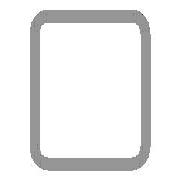
# Autodesk Inventor part: DIN EN 10219-2 - 80 x 80 x 5  - 108,9
Saved by Autodesk Inventor 2025.3 (Build 293356000, 356)
## iProperties
IsCustomPart: 1
Created: 2024-01-20
Part Number: DIN EN 10219-2 - 80 x 80 x 5  - 108,9
Material: Aluminium 6061
Description: Kaltgeformte, geschweißte Baustahl-Hohlprofile aus unlegiertem Feinkorn-Baustahl
Document SubType Name: Modeling
Standard: DIN EN 10219-2
Designer: sebas
Standard Revision: 2006-07
Standards Organization: DIN
Language: de-DE
Size Designation: 80 x 80 x 5  - 108,9
Categories: <MemberInstance><Categories><Category DisplayName="Profile" InternalName="089c4875-fa83-4c05-b084-43b9cc11f5ed" Mnemonic="GRDR"><CategoryParameter DisplayName="Masse pro Längeneinheit" InternalName="0bb95a10-148f-4027-a459-38d7b056702a" Mnemonic="shpmass"/><CategoryParameter DisplayName="Querschnittsfläche" InternalName="1ff91680-64b0-4202-b9a3-7fd3f94bba3b" Mnemonic="secarea"/><CategoryParameter DisplayName="Trägheitsradius (x)" InternalName="25778675-03e9-40c1-b6a8-4a9ed693320d" Mnemonic="gyrradx"/><CategoryParameter DisplayName="Torsion-Festigkeitsmodul" InternalName="26c1ec35-5026-4c63-ad0a-751cf684a536" Mnemonic="torrigmod"/><CategoryParameter DisplayName="Abstand zum Schwerpunkt X-X" InternalName="26c9bdb8-9c79-4b4f-a92e-8e197583c9c4" Mnemonic="grcendistX"/><CategoryParameter DisplayName="Alte Varianten-ID" InternalName="340afe4f-75d7-48d3-ab7d-943f3c3da468" Mnemonic="LegacyMemberID"/><CategoryParameter DisplayName="Basislänge" InternalName="42e34263-8f20-4d0e-ad48-bf1385b87c24" Mnemonic="shplen"/><CategoryParameter DisplayName="Trägheitsmoment (y)" InternalName="4b9f58ea-bced-460e-81ea-3d29ca5a49e3" Mnemonic="inermomy"/><CategoryParameter DisplayName="Trägheitsmoment (x)" InternalName="4cd780bc-73d7-43ac-917a-579e5cbd684d" Mnemonic="inermomx"/><CategoryParameter DisplayName="Benutzerdefinierter Basispunkt" InternalName="4f1d1b73-316d-484b-a3df-9cbabb16eb77" Mnemonic="shpBasePoint"/><CategoryParameter DisplayName="Objekthöhe" InternalName="50274e7d-5ac0-4796-92cb-c59e54983c67" Mnemonic="shpheig"/><CategoryParameter DisplayName="Widerstandsmoment (y)" InternalName="59eaa5e9-d227-48dc-b6c1-6920f96e0f95" Mnemonic="secmody"/><CategoryParameter DisplayName="Schnittbezeichnung" InternalName="5a64d034-428d-49c8-ba32-7619764de20f" Mnemonic="shpdes"/><CategoryParameter DisplayName="Widerstandsmoment (x)" InternalName="72cfad18-cf51-4ed4-aaa7-c6b224f8419f" Mnemonic="secmodx"/><CategoryParameter DisplayName="Drehrissmodul" InternalName="7c55a8dc-8844-49f9-a867-cc677b30ec9a" Mnemonic="torsecmod"/><CategoryParameter DisplayName="Objektbreite" InternalName="7c717d54-a18f-4666-b4d4-573cce22c62c" Mnemonic="shpwdth"/><CategoryParameter DisplayName="Zweite Objektdicke" InternalName="9251a8e1-85fd-4e47-af99-afdb762317d9" Mnemonic="shpthick2"/><CategoryParameter DisplayName="GG Erstellt" InternalName="9c666724-f362-4ea7-ac62-f6a007de5c69" Mnemonic="shpFGAuto"/><CategoryParameter DisplayName="Abstand zum Schwerpunkt Y-Y" InternalName="bcc4fb17-7af4-436a-8f8c-d0aa3b0248c5" Mnemonic="grcendistY"/><CategoryParameter DisplayName="Trägheitsradius (y)" InternalName="bfa18ebe-1636-4dbe-8d42-b263e0b73184" Mnemonic="gyrrady"/><CategoryParameter DisplayName="Objektdicke" InternalName="d109cf76-8eb4-42fc-9800-4409734adc67" Mnemonic="shpthick"/><CategoryParameter DisplayName="Koeffizient für Schubverschiebung" InternalName="de4c90c6-aaa8-468f-a335-6737b311b5d3" Mnemonic="shdispc"/><Category DisplayName="Vierkantrohre (quadratisch/rechteckig)" InternalName="afc8e2d8-05d6-4609-8807-f98a9b7d2ed0" Mnemonic="SQRSHP"><CategoryParameter DisplayName="Querschnittsfläche" InternalName="2f7f79dd-983c-4263-802a-5b6a1495fdc5" Mnemonic="secarea"/><CategoryParameter DisplayName="Widerstandsmoment (x)" InternalName="50d965a6-04bf-46b9-8ace-861858d348e6" Mnemonic="secmodx"/><CategoryParameter DisplayName="Widerstandsmoment (y)" InternalName="5106aeac-54a2-4159-a9af-8933dd39dba2" Mnemonic="secmody"/><CategoryParameter DisplayName="Objektdicke" InternalName="52712fc5-f4ee-4eda-b3f2-6fce82c26419" Mnemonic="shpthick"/><CategoryParameter DisplayName="Trägheitsmoment (y)" InternalName="55ec8510-8276-4c45-8f10-594e0fee7eb3" Mnemonic="inermomy"/><CategoryParameter DisplayName="Trägheitsradius (x)" InternalName="56c89926-a299-4389-a862-ac94c9691272" Mnemonic="gyrradx"/><CategoryParameter DisplayName="Radius" InternalName="5d8d062c-e28e-41c1-98da-8e5fee36da1a" Mnemonic="shprad"/><CategoryParameter DisplayName="Trägheitsmoment (x)" InternalName="8c4637b6-6b69-4878-9d5d-26a32185d655" Mnemonic="inermomx"/><CategoryParameter DisplayName="Objektbreite" InternalName="8c8a1782-5e80-4d77-858b-304b1c0ad1fd" Mnemonic="shpwdth"/><CategoryParameter DisplayName="Trägheitsradius (y)" InternalName="fa48a7f5-f030-40f9-a60b-de8a845b7104" Mnemonic="gyrrady"/></Category></Category><Category DisplayName="Datentyp" InternalName="23b78d0f-2648-40c6-8793-ca6db495c9e8" Mnemonic="DATATYPE"><CategoryParameter DisplayName="Anzeigename" InternalName="05415f3d-3907-474b-a020-eb9d644f4cf3" Mnemonic="DISPLAYNAME"/><CategoryParameter DisplayName="Norm" InternalName="0c0a119c-1e12-4c84-803f-101930972f5e" Mnemonic="STANDARD"/><CategoryParameter DisplayName="Beschreibung" InternalName="13903e3d-64b1-4950-80da-f627842ea37f" Mnemonic="DESCRIPTION"/><CategoryParameter DisplayName="Bezeichnung" InternalName="2675968c-4ce5-49e0-a4f5-552d29089031" Mnemonic="DESIGNATION"/><CategoryParameter DisplayName="Standardzeile" InternalName="2af9ec52-faaa-4026-b378-f9fa4afca842" Mnemonic="DEFAULTROW"/><CategoryParameter DisplayName="Ordnername" InternalName="3f06958e-8713-4116-9be7-ed6184ecc97b" Mnemonic="FOLDERNAME"/><CategoryParameter DisplayName="Revisionsanleitung" InternalName="45a75005-10b1-4dfc-8d6d-dfe629f0b93c" Mnemonic="REVISIONGUID"/><CategoryParameter DisplayName="Dateiname" InternalName="8b46a4cc-9585-4fed-90c3-899f57e09a73" Mnemonic="FILENAME"/><CategoryParameter DisplayName="Normungsorganisation" InternalName="8f5914e1-4693-403f-8ab5-d37768198c9d" Mnemonic="STDSORG"/><CategoryParameter DisplayName="Gruppenversion" InternalName="914462f6-6e19-4b14-ba84-155b9680b1d0" Mnemonic="FAMILYREVISION"/><CategoryParameter DisplayName="Normrevision" InternalName="91d5a463-65c2-4fde-b823-3b7fea5e8e17" Mnemonic="STANDARDREVISION"/><CategoryParameter DisplayName="Variantenrevision" InternalName="a65d44b9-392f-4f4f-857b-e4b3d54996fe" Mnemonic="MEMBERREVISION"/><CategoryParameter DisplayName="ClipFormat" InternalName="bc51e27b-3422-4e78-93ef-cec197ddf230" Mnemonic="CLIPFORMAT"/><CategoryParameter DisplayName="Hersteller" InternalName="cd6c7a72-a28a-4e50-99a9-2c7f4e13e5ad" Mnemonic="MANUFACTURER"/><CategoryParameter DisplayName="InternerName" InternalName="cf1d0246-76d9-4b4a-8305-fa0409afb5c1" Mnemonic="INTERNALNAME"/><CategoryParameter DisplayName="IstMetrisch" InternalName="e2385c5b-1ea4-4823-96a8-8de651266ec3" Mnemonic="ISMETRIC"/><Category DisplayName="Bauteil" InternalName="c0e0b642-3bcb-4cc8-9e80-f96d35c4afa4" Mnemonic="PART"><CategoryParameter DisplayName="Bauteilnummer" InternalName="016b6077-bfbe-49bd-92c9-d8d59c39c941" Mnemonic="PARTNUMBER"/><CategoryParameter DisplayName="Bestandsnummer" InternalName="4dba7c1c-e26c-444e-836c-b08b433409a8" Mnemonic="STOCKNUMBER"/><CategoryParameter DisplayName="Materialschlüssel" InternalName="5c9a8adb-dd2b-4535-b97f-0a94a95fe41f" Mnemonic="MATERIALKEY"/><CategoryParameter DisplayName="Material" InternalName="818a152a-d3c3-49ca-80ee-df7d91421b8e" Mnemonic="MATERIAL"/></Category></Category><Category DisplayName="ÄltereVersionenzuweisen" InternalName="cd87c42b-3e48-431e-b5c0-1cbeb14dfe77" Mnemonic="LEGACYMAP"><CategoryParameter DisplayName="Eindeutige DA-Varianten-ID" InternalName="0918ad47-427f-4fed-ae26-24c81c58f590" Mnemonic="DACOOKIE"/><CategoryParameter DisplayName="ID zusammenführen" InternalName="0ee8fb18-e2ed-4f39-96f6-1f4b5f50aa71" Mnemonic="MERGE11"/><CategoryParameter DisplayName="Eindeutige CC-Varianten-ID" InternalName="5193edd4-b2b0-4ab4-9d54-de900eee34e0" Mnemonic="CCCOOKIE"/><CategoryParameter DisplayName="ID aufteilen" InternalName="72b5c83c-be7f-45c4-ae51-9160ea6deb26" Mnemonic="SPLIT"/><CategoryParameter DisplayName="VarianteID" InternalName="8e5e0294-fc51-4c8f-b3d7-003dc5ed94f6" Mnemonic="MEMBERID"/><CategoryParameter DisplayName="Katalogname" InternalName="d99d1e27-aa94-4de2-af4c-c348882a6f4f" Mnemonic="CATALOGNAME"/><CategoryParameter DisplayName="Gruppennummer" InternalName="e705e1f4-09cb-413e-91f9-551b4188271e" Mnemonic="FAMILYNUMBER"/></Category></Categories><FamilyTemplate Id="gp0601"><FamilyTemplateParameters><FamilyTemplateParameter ObjectType="kUserParameterObject" ValueType="xs:double" Id="1" ObjectReferenceKey="G_H"/><FamilyTemplateParameter ObjectType="kUserParameterObject" ValueType="xs:double" Id="2" ObjectReferenceKey="B_L"/><FamilyTemplateParameter ObjectType="kUserParameterObject" ValueType="xs:double" Id="6" ObjectReferenceKey="G_W"/><FamilyTemplateParameter ObjectType="kUserParameterObject" ValueType="xs:double" Id="7" ObjectReferenceKey="G_T"/><FamilyTemplateParameter ObjectType="kUserParameterObject" ValueType="xs:double" Id="8" ObjectReferenceKey="G_IR"/><FamilyTemplateParameter ObjectType="kPropertyObject" ValueType="xs:string" Id="100" ObjectReferenceKey="{32853F0F-3444-11d1-9E93-0060B03C1CA6}" SubObjectId="52"/><FamilyTemplateParameter ObjectType="kPropertyObject" ValueType="xs:string" Id="105" ObjectReferenceKey="{32853F0F-3444-11d1-9E93-0060B03C1CA6}" SubObjectId="5"/><FamilyTemplateParameter ObjectType="kPartComponentDefinitionObject" ValueType="xs:string" Id="110" SubObjectId="Material"/><FamilyTemplateParameter ObjectType="kPropertyObject" ValueType="xs:string" Id="112" ObjectReferenceKey="{32853F0F-3444-11d1-9E93-0060B03C1CA6}" SubObjectId="55"/></FamilyTemplateParameters></FamilyTemplate><CategoryParameterMap><ParamToTemplateMap><ParamToTemplate CategoryParameter="//CategoryParameter[@InternalName='05415f3d-3907-474b-a020-eb9d644f4cf3']" ConstantValue="DIN EN 10219-2 (Square Hollow Section - Cold Formed)"/><ParamToTemplate CategoryParameter="//CategoryParameter[@InternalName='cf1d0246-76d9-4b4a-8305-fa0409afb5c1']" ConstantValue="f4eb4807-7530-48bf-9740-f5a60eee53a8"/><ParamToTemplate CategoryParameter="//CategoryParameter[@InternalName='3f06958e-8713-4116-9be7-ed6184ecc97b']" ConstantValue="DIN EN 10219-2(1)"/><ParamToTemplate CategoryParameter="//CategoryParameter[@InternalName='914462f6-6e19-4b14-ba84-155b9680b1d0']" ConstantValue="10"/><ParamToTemplate CategoryParameter="//CategoryParameter[@InternalName='bc51e27b-3422-4e78-93ef-cec197ddf230']" ConstantValue="CF_INVENTOR.STDPARTS"/><ParamToTemplate CategoryParameter="//CategoryParameter[@InternalName='e2385c5b-1ea4-4823-96a8-8de651266ec3']" ConstantValue="true"/><ParamToTemplate CategoryParameter="//CategoryParameter[@InternalName='13903e3d-64b1-4950-80da-f627842ea37f']" ConstantValue="Cold formed welded structural hollow sections of non-alloy and fine grain structural steel"/><ParamToTemplate CategoryParameter="//CategoryParameter[@InternalName='8f5914e1-4693-403f-8ab5-d37768198c9d']" ConstantValue="DIN"/><ParamToTemplate CategoryParameter="//CategoryParameter[@InternalName='0c0a119c-1e12-4c84-803f-101930972f5e']" ConstantValue="DIN EN 10219-2"/><ParamToTemplate CategoryParameter="//CategoryParameter[@InternalName='cd6c7a72-a28a-4e50-99a9-2c7f4e13e5ad']" TemplateParameter="104"/><ParamToTemplate CategoryParameter="//CategoryParameter[@InternalName='91d5a463-65c2-4fde-b823-3b7fea5e8e17']" ConstantValue="2006-07"/><ParamToTemplate CategoryParameter="//CategoryParameter[@InternalName='45a75005-10b1-4dfc-8d6d-dfe629f0b93c']" ConstantValue="fa0180ad-9900-4c48-9c99-ee51de72b725"/><ParamToTemplate CategoryParameter="//CategoryParameter[@InternalName='2af9ec52-faaa-4026-b378-f9fa4afca842']" ConstantValue="1"/><ParamToTemplate CategoryParameter="//CategoryParameter[@InternalName='9c666724-f362-4ea7-ac62-f6a007de5c69']" ConstantValue="1"/><ParamToTemplate CategoryParameter="//CategoryParameter[@InternalName='d99d1e27-aa94-4de2-af4c-c348882a6f4f']" ConstantValue="BSI"/><ParamToTemplate CategoryParameter="//CategoryParameter[@InternalName='e705e1f4-09cb-413e-91f9-551b4188271e']" ConstantValue="158"/><ParamToTemplate CategoryParameter="//CategoryParameter[@InternalName='8b46a4cc-9585-4fed-90c3-899f57e09a73']" ConstantValue="DIN EN 10219-2 - 80 x 80 x 5  - 108,9"/><ParamToTemplate CategoryParameter="//CategoryParameter[@InternalName='a65d44b9-392f-4f4f-857b-e4b3d54996fe']" ConstantValue="49229FD5-5431-4EE6-B6F3-2C28CB392A87"/><ParamToTemplate CategoryParameter="//CategoryParameter[@InternalName='8c4637b6-6b69-4878-9d5d-26a32185d655']" ConstantValue="131"/><ParamToTemplate CategoryParameter="//CategoryParameter[@InternalName='56c89926-a299-4389-a862-ac94c9691272']" ConstantValue="30,3"/><ParamToTemplate CategoryParameter="//CategoryParameter[@InternalName='50d965a6-04bf-46b9-8ace-861858d348e6']" ConstantValue="32,9"/><ParamToTemplate CategoryParameter="//CategoryParameter[@InternalName='2f7f79dd-983c-4263-802a-5b6a1495fdc5']" ConstantValue="14,4"/><ParamToTemplate CategoryParameter="//CategoryParameter[@InternalName='7c55a8dc-8844-49f9-a867-cc677b30ec9a']" ConstantValue="49,7"/><ParamToTemplate CategoryParameter="//CategoryParameter[@InternalName='26c1ec35-5026-4c63-ad0a-751cf684a536']" ConstantValue="218"/><ParamToTemplate CategoryParameter="//CategoryParameter[@InternalName='de4c90c6-aaa8-468f-a335-6737b311b5d3']" ConstantValue="2,1646563"/><ParamToTemplate CategoryParameter="//CategoryParameter[@InternalName='5a64d034-428d-49c8-ba32-7619764de20f']" ConstantValue="80 x 80 x 5"/><ParamToTemplate CategoryParameter="//CategoryParameter[@InternalName='8e5e0294-fc51-4c8f-b3d7-003dc5ed94f6']" ConstantValue="32"/><ParamToTemplate CategoryParameter="//CategoryParameter[@InternalName='42e34263-8f20-4d0e-ad48-bf1385b87c24']" TemplateParameter="2"/><ParamToTemplate CategoryParameter="//CategoryParameter[@InternalName='2675968c-4ce5-49e0-a4f5-552d29089031']" TemplateParameter="100"/><ParamToTemplate CategoryParameter="//CategoryParameter[@InternalName='50274e7d-5ac0-4796-92cb-c59e54983c67']" TemplateParameter="1"/><ParamToTemplate CategoryParameter="//CategoryParameter[@InternalName='52712fc5-f4ee-4eda-b3f2-6fce82c26419']" TemplateParameter="7"/><ParamToTemplate CategoryParameter="//CategoryParameter[@InternalName='8c8a1782-5e80-4d77-858b-304b1c0ad1fd']" TemplateParameter="6"/><ParamToTemplate CategoryParameter="//CategoryParameter[@InternalName='818a152a-d3c3-49ca-80ee-df7d91421b8e']" TemplateParameter="110"/><ParamToTemplate CategoryParameter="//CategoryParameter[@InternalName='016b6077-bfbe-49bd-92c9-d8d59c39c941']" TemplateParameter="105"/><ParamToTemplate CategoryParameter="//CategoryParameter[@InternalName='4dba7c1c-e26c-444e-836c-b08b433409a8']" TemplateParameter="112"/></ParamToTemplateMap></CategoryParameterMap></MemberInstance>
Stock Number: 80 x 80 x 5
Mass: 781.823 g
Surface Area: 1166.84 cm^2
Volume: 289.564 cm^3
Density: 2.7 g/cm^3
Appearance: Aluminium - flach
G_L: 108,900 mm
Author: sebas
Autodesk Inventor part; units mm, degrees
ref_plane "YZ Plane" through (0, 0, 0) normal (1, 0, 0) x (0, 1, 0)
ref_plane "Startebene" through (0, 0, 0) normal (0, 0, 1) x (1, 0, 0)
ref_plane "Endebene" through (0, 0, 108.9) normal (0, 0, 1) x (1, 0, 0)
sketch "Skizze" plane through (0, 0, 0) normal (0, 0, 1) x (1, 0, 0)
  line L0 (-60, -50) -> (-60, 50)
  line L1 (-50, 60) -> (50, 60)
  line L2 (60, 50) -> (60, -50)
  line L3 (50, -60) -> (-50, -60)
  arc A0 (-60, -50) -> (-50, -60) centre (-50, -50) ccw
  arc A1 (-50, 60) -> (-60, 50) centre (-50, 50) ccw
  arc A2 (60, 50) -> (50, 60) centre (50, 50) ccw
  arc A3 (50, -60) -> (60, -50) centre (50, -50) ccw
  arc A4 (-50, 55) -> (-55, 50) centre (-50, 50) ccw
  line L4 (-50, 55) -> (50, 55)
  arc A5 (55, 50) -> (50, 55) centre (50, 50) ccw
  line L5 (55, 50) -> (55, -50)
  arc A6 (50, -55) -> (55, -50) centre (50, -50) ccw
  line L6 (50, -55) -> (-50, -55)
  arc A7 (-55, -50) -> (-50, -55) centre (-50, -50) ccw
  line L7 (-55, -50) -> (-55, 50)
  line L8 (0, 86.8995) -> (0, -86.8995) construction
  line L9 (-86.8995, 0) -> (86.8995, 0) construction
  dimension "d7" = 10
  dimension "d10" = 120
  dimension "d11" = 120
  dimension "d12" = 5
  dimension "d15" = 60
  dimension "d16" = 60
  constraints: 16 end point, 16 point on circle, 8 centre point, 8 tangent, 4 parallel, 3 equal radius, 2 perpendicular, 7 other
  measures "d7" radius of A0
  measures "d10" distance between parallel lines of L1 L3
  measures "d11" distance between parallel lines of L0 L2
  measures "d12" distance between parallel lines of L2 L5
  measures "d15" distance between parallel lines of L1 L9
  measures "d16" distance between parallel lines of L8 L2
extrude "Körper" add sketch "Skizze" along normal up to surface (108.9 mm away) from surface at 0
sketch "Sketch3" plane through (0, 0, 0) normal (0, 0, 1) x (1, 0, 0)
  line L0 (0, 0) -> (10, 0)
ref_plane "Work Plane3" through (0, 0, 0) normal (0, -1, 0) x (1, 0, 0)
sketch "Skizze5" plane through (-60, 50, 0) normal (-1, 0, 0) x (0, 0, 1)
  line L0 (0, -134) -> (0, 34) projected
  line L1 (-21.78, -50) -> (130.68, -50) projected
  line L2 (107.2, -56.5) -> (92.2, -56.5)
  line L3 (92.2, -56.5) -> (92.2, -77.5)
  line L4 (92.2, -77.5) -> (107.2, -77.5)
  line L5 (107.2, -77.5) -> (107.2, -56.5)
  line L6 (108.9, -100) -> (108.9, 0) projected
  line L7 (0, -110) -> (108.9, -110) projected
  line L8 (81.2, -36.2) -> (63.6, -36.2)
  line L9 (63.6, -36.2) -> (63.6, -63.8)
  line L10 (63.6, -63.8) -> (81.2, -63.8)
  line L11 (81.2, -63.8) -> (81.2, -36.2)
  line L12 (72.4, -36.2) -> (72.4, -63.8)
  circle A0 centre (72.4, -60.5) radius 5
  line L13 (81.2, -50) -> (63.6, -50)
  line L14 (0, 10) -> (108.9, 10) projected
  circle A1 centre (72.4, -39.5) radius 5
  point P0 (0, -50)
  point P1 (68.6437, -36.2)
  point P2 (68.6437, -63.8)
  point P3 (76.1563, -63.8)
  point P4 (76.1563, -36.2)
  dimension "d19" = 21
  dimension "d20" = 15
  dimension "d21" = 1.7
  dimension "d22" = 32.5
  dimension "d23" = 27.6
  dimension "d24" = 17.6
  dimension "d25" = 27.7
  dimension "d27" = 10
  dimension "d30" = 10
  dimension "d31" = 21
  dimension "d32" = 49.5
  dimension "d33" = 46.2
  constraints: 20 end point, 4 midpoint, 4 parallel, 2 centre point, 2 perpendicular, 2 point on line, 1 horizontal
  measures "d19" distance of L4.end L2.start
  measures "d20" distance between parallel lines of L3 L5
  measures "d21" distance between parallel lines of L6 L5
  measures "d22" distance between parallel lines of L7 L4
  measures "d23" distance of L10.end L8.start
  measures "d24" distance between parallel lines of L9 L11
  measures "d25" distance between parallel lines of L6 L11
  measures "d27" diameter of A0
  measures "d30" diameter of A1
  measures "d31" distance of A0.centre A1.centre
  measures "d32" distance from line of L14 A1.centre
  measures "d33" distance between parallel lines of L14 L8
extrude "Extrusion3" cut sketch "Skizze5" against normal up to surface (5 mm away)
fillet "Rundung4" radius 2 8 edges at (-57.5, 13.8, 63.6) (-57.5, 13.8, 81.2) (-57.5, -13.8, 81.2) (-57.5, -13.8, 63.6) (-57.5, -27.5, 92.2) (-57.5, -27.5, 107.2) (-57.5, -6.5, 107.2) (-57.5, -6.5, 92.2)
sketch "Skizze6" plane through (0, 0, 0) normal (0, 0, -1) x (-1, 0, 0)
  line L0 (-34.0882, -39.852) -> (-23.0882, -39.852)
  arc A0 (-40.0882, -33.852) -> (-34.0882, -39.852) centre (-34.0882, -33.852) ccw
  line L1 (-40.0882, -22.852) -> (-40.0882, -33.852)
  circle A1 centre (-31.908, -31.6718) radius 3
  line L2 (-26.0882, -31.852) -> (-26.0882, -36.852)
  arc A2 (-26.0882, -36.852) -> (-23.0882, -39.852) centre (-23.0882, -36.852) ccw
  arc A3 (-26.0882, -31.852) -> (-26.1825, -30.7923) centre (-32.0882, -31.852) ccw
  arc A4 (-26.7535, -30.2637) -> (-25.8422, -30.852) centre (-25.8422, -29.852) ccw
  arc A5 (-26.7535, -30.2637) -> (-33.5882, -25.852) centre (-33.5882, -33.352) ccw
  line L3 (-33.5882, -25.602) -> (-36.0882, -25.602)
  line L4 (-36.0882, -25.852) -> (-33.5882, -25.852)
  arc A6 (-40.0882, -21.852) -> (-36.0882, -25.852) centre (-36.0882, -21.852) ccw
  line L5 (-40.0882, 22.398) -> (-40.0882, -21.852)
  arc A7 (-36.3382, 26.148) -> (-40.0882, 22.398) centre (-36.3382, 22.398) ccw
  line L6 (-31.8382, 26.148) -> (-36.3382, 26.148)
  arc A8 (-31.8382, 26.148) -> (-27.5882, 30.398) centre (-31.8382, 30.398) ccw
  line L7 (-27.5882, 40.148) -> (-27.5882, 30.398)
  line L8 (-25.8422, -30.852) -> (-21.5882, -30.852)
  arc A9 (-17.0882, -35.352) -> (-21.5882, -30.852) centre (-21.5882, -35.352) ccw
  line L9 (-17.0882, -35.352) -> (-17.0882, -38.852)
  arc A10 (-17.0882, -38.852) -> (-16.0882, -39.852) centre (-16.0882, -38.852) ccw
  line L10 (-16.0882, -39.852) -> (21.9118, -39.852)
  arc A11 (21.9118, -39.852) -> (25.9118, -35.852) centre (21.9118, -35.852) ccw
  line L11 (25.9118, -35.852) -> (25.9118, -33.352)
  arc A12 (30.3236, -26.5173) -> (25.9118, -33.352) centre (33.4118, -33.352) ccw
  arc A13 (30.3236, -26.5173) -> (30.9118, -25.606) centre (29.9118, -25.606) ccw
  line L12 (30.9118, -25.606) -> (30.9118, -21.352)
  arc A14 (35.4118, -16.852) -> (30.9118, -21.352) centre (35.4118, -21.352) ccw
  line L13 (35.4118, -16.852) -> (38.9118, -16.852)
  arc A15 (38.9118, -16.852) -> (39.9118, -15.852) centre (38.9118, -15.852) ccw
  line L14 (39.9118, -15.852) -> (39.9118, 22.148)
  arc A16 (39.9118, 22.148) -> (35.9118, 26.148) centre (35.9118, 22.148) ccw
  line L15 (35.9118, 26.148) -> (33.4118, 26.148)
  arc A17 (26.5771, 30.5598) -> (33.4118, 26.148) centre (33.4118, 33.648) ccw
  arc A18 (26.5771, 30.5598) -> (25.6659, 31.148) centre (25.6659, 30.148) ccw
  line L16 (25.6659, 31.148) -> (21.4118, 31.148)
  arc A19 (16.9118, 35.648) -> (21.4118, 31.148) centre (21.4118, 35.648) ccw
  line L17 (16.9118, 35.648) -> (16.9118, 39.148)
  arc A20 (16.9118, 39.148) -> (15.9118, 40.148) centre (15.9118, 39.148) ccw
  line L18 (15.9118, 40.148) -> (-27.5882, 40.148)
  arc A21 (-40.0882, -22.852) -> (-37.0882, -25.852) centre (-37.0882, -22.852) ccw
  line L19 (-50.0882, -54.852) -> (49.9118, -54.852)
  arc A22 (-55.0882, -49.852) -> (-50.0882, -54.852) centre (-50.0882, -49.852) ccw
  line L20 (-55.0882, 50.148) -> (-55.0882, -49.852)
  circle A23 centre (-31.908, -31.6718) radius 3
  arc A24 (-26.0882, -33.352) -> (-33.5882, -25.852) centre (-33.5882, -33.352) ccw
  line L21 (-26.0882, -33.352) -> (-26.0882, -39.852)
  line L22 (-33.5882, -25.852) -> (-55.0882, -25.852)
  line L23 (-26.0882, -39.852) -> (-26.0882, -54.852)
  line L24 (0.6205, 84.6205) -> (0.6205, -83.3795)
  line L25 (-83.3795, 0.6205) -> (84.6205, 0.6205)
  arc A25 (33.4118, -25.852) -> (25.9118, -33.352) centre (33.4118, -33.352) ccw
  circle A26 centre (31.7316, -31.6718) radius 3
  circle A27 centre (31.7316, 31.9678) radius 3
  circle A28 centre (-31.908, 31.9678) radius 3
  circle A29 centre (31.7316, -31.6718) radius 3
  circle A30 centre (31.7316, 31.9678) radius 3
  arc A31 (25.9118, 33.648) -> (33.4118, 26.148) centre (33.4118, 33.648) ccw
  circle A32 centre (-31.908, 31.9678) radius 3
  line L26 (49.9118, 55.148) -> (-50.0882, 55.148)
  line L27 (54.9118, -49.852) -> (54.9118, 50.148)
  line L28 (-27.5882, 30.398) -> (-27.5882, 55.148)
  line L29 (-31.8382, 26.148) -> (-55.0882, 26.148)
  line L30 (25.9118, -33.352) -> (25.9118, -54.852)
  line L31 (33.4118, -25.852) -> (54.9118, -25.852)
  line L32 (25.9118, 33.648) -> (25.9118, 55.148)
  line L33 (33.4118, 26.148) -> (54.9118, 26.148)
  arc A33 (-31.8382, 26.148) -> (-27.5882, 30.398) centre (-31.8382, 30.398) ccw
  arc A34 (-29.8589, 34.159) -> (-34.1435, 33.9685) centre (-31.8382, 30.398) ccw
  arc A35 (49.9118, -54.852) -> (54.9118, -49.852) centre (49.9118, -49.852) ccw
  arc A36 (-50.0882, 55.148) -> (-55.0882, 50.148) centre (-50.0882, 50.148) ccw
  arc A37 (54.9118, 50.148) -> (49.9118, 55.148) centre (49.9118, 50.148) ccw
  line L34 (-55, -50) -> (-55, 50) projected
  point P0 (-26.8765, -29.477)
  point P1 (0.6205, 0.6205)
  constraints: 68 end point, 60 point on circle, 36 centre point, 17 point on line, 8 coincident, 6 concentric, 3 perpendicular, 2 tangent, 1 horizontal, 1 parallel, 1 vertical, 11 other
extrude "Extrusion6" add sketch "Skizze6" against normal blind 18 contours A0 L1 L22 L4 A5 A24 L2 L21 L0 | L0 L23 L19 A22 L20 L22 L1 A0 | L30 L11 A12 A25 L31 L27 A35 L19 | L29 L20 A36 L26 L28 L7 A8 L6 | L26 A37 L27 L33 L15 A17 A31 L32
extrude "Extrusion7" cut sketch "Skizze6" against normal blind 8 contours A0 L1 L22 L4 A5 A24 L2 L21 L0 | L0 L23 L19 A22 L20 L22 L1 A0 | L30 L11 A12 A25 L31 L27 A35 L19 | L29 L20 A36 L26 L28 L7 A8 L6 | L26 A37 L27 L33 L15 A17 A31 L32
sketch "Skizze8" plane through (-50, -60, 108.9) normal (0, 0, 1) x (1, 0, 0)
  arc A0 (0.1533, 120.0745) -> (-9.8467, 110.0745) centre (0.1533, 110.0745) ccw
  line L0 (0.1533, 115.0745) -> (100.1533, 115.0745)
  line L1 (0.1533, 120.0745) -> (100.1533, 120.0745)
  arc A1 (105.1533, 110.0745) -> (100.1533, 115.0745) centre (100.1533, 110.0745) ccw
  arc A2 (110.1533, 110.0745) -> (100.1533, 120.0745) centre (100.1533, 110.0745) ccw
  line L2 (-35.2418, 60.0745) -> (138.5572, 60.0745) construction
  line L3 (110.1533, 110.0745) -> (110.1533, 10.0745)
  line L4 (105.1533, 110.0745) -> (105.1533, 10.0745)
  line L5 (100.1533, 0.0745) -> (0.1533, 0.0745)
  line L6 (50.1533, 145.44) -> (50.1533, -28.3589) construction
  arc A3 (-9.8467, 10.0745) -> (0.1533, 0.0745) centre (0.1533, 10.0745) ccw
  line L7 (-9.8467, 10.0745) -> (-9.8467, 110.0745)
  line L8 (-4.8467, 10.0745) -> (-4.8467, 110.0745)
  arc A4 (0.1533, 115.0745) -> (-4.8467, 110.0745) centre (0.1533, 110.0745) ccw
  arc A5 (-4.8467, 10.0745) -> (0.1533, 5.0745) centre (0.1533, 10.0745) ccw
  line L9 (100.1533, 5.0745) -> (0.1533, 5.0745)
  arc A6 (100.1533, 5.0745) -> (105.1533, 10.0745) centre (100.1533, 10.0745) ccw
  arc A7 (100.1533, 0.0745) -> (110.1533, 10.0745) centre (100.1533, 10.0745) ccw
  arc A8 (95.1533, 22.5745) -> (87.6533, 15.0745) centre (95.1533, 15.0745) ccw
  line L10 (95.1533, 22.5745) -> (105.1533, 22.5745)
  line L11 (87.6533, 15.0745) -> (87.6533, 5.0745)
  line L12 (95.1533, 97.5745) -> (105.1533, 97.5745)
  arc A9 (87.6533, 105.0745) -> (95.1533, 97.5745) centre (95.1533, 105.0745) ccw
  line L13 (87.6533, 105.0745) -> (87.6533, 115.0745)
  arc A10 (12.6533, 15.0745) -> (5.1533, 22.5745) centre (5.1533, 15.0745) ccw
  line L14 (5.1533, 22.5745) -> (-4.8467, 22.5745)
  line L15 (12.6533, 15.0745) -> (12.6533, 5.0745)
  line L16 (5.1533, 97.5745) -> (-4.8467, 97.5745)
  arc A11 (5.1533, 97.5745) -> (12.6533, 105.0745) centre (5.1533, 105.0745) ccw
  line L17 (12.6533, 105.0745) -> (12.6533, 115.0745)
  point P0 (50, 60)
  point P1 (50.1341, 60.0169)
  point P2 (-4.8467, 22.5745)
  point P3 (12.6533, 115.0745)
  dimension "d60" = 10
  dimension "d61" = 120
  dimension "d62" = 120
  dimension "d63" = 5
  dimension "d64" = 60
  dimension "d65" = 60
  dimension "d66" = 10
  dimension "d67" = 10
  dimension "d68" = 15
  constraints: 36 end point, 24 point on circle, 18 symmetric about line, 12 centre point, 10 tangent, 4 parallel, 4 perpendicular, 3 equal radius, 2 point on line, 1 coincident, 10 other
  measures "d60" radius of A3
  measures "d61" distance between parallel lines of L1 L5
  measures "d62" distance between parallel lines of L7 L3
  measures "d63" distance between parallel lines of L3 L4
  measures "d64" distance between parallel lines of L1 L2
  measures "d65" distance between parallel lines of L6 L3
  measures "d66" distance from line of L4 point (95.153, 15.075)
  measures "d67" distance from line of L9 point (95.153, 15.075)
  measures "d68" diameter of A8
extrude "Extrusion8" add sketch "Skizze8" against normal blind 20 contours L0 L17 A11 L16 L8 A4 | L0 A1 L4 L12 A9 L13 | L14 A10 L15 L9 A5 L8 | L4 A6 L9 L11 A8 L10
hole "Bohrung2" at (-44.8467, 45.0745, 108.9) at (-44.8467, -44.9255, 108.9) at (45.1533, 45.0745, 108.9) at (45.1533, -44.9255, 108.9) direction (0, 0, -1) diameter 8 depth 20
sketch "Sketch4" plane through (0, 0, 0) normal (0, -1, 0) x (1, 0, 0)
  line L0 (-62, 0) -> (22, 0) projected
  line L1 (-62, 108.9) -> (22, 108.9) projected
  dimension "d18" = 108.9
  measures "d18" distance between parallel lines of L0 L1
equation "\"d7\" = G_IR"
equation "\"d12\" = G_T"
equation "\"d15\" = 0.5 * d10"
equation "\"d16\" = 0.5 * d11"
equation "\"d3\" = G_L"
equation "\"d60\" = d69"
equation "\"d63\" = d70"
equation "\"d64\" = 0.5 * d61"
equation "\"d65\" = 0.5 * d62"
equation "\"G_T\" = 5"
equation "\"G_IR\" = 10"
equation "\"G_L\" = d18"
equation "\"G_OFFSET_START\" = 0"
equation "\"G_OFFSET_END\" = 0"
equation "\"d14\" = G_OFFSET_END + B_L"
equation "\"B_L\" = 108.9"
equation "\"d69\" = 10"
equation "\"d70\" = 5"
body "Solid1"
